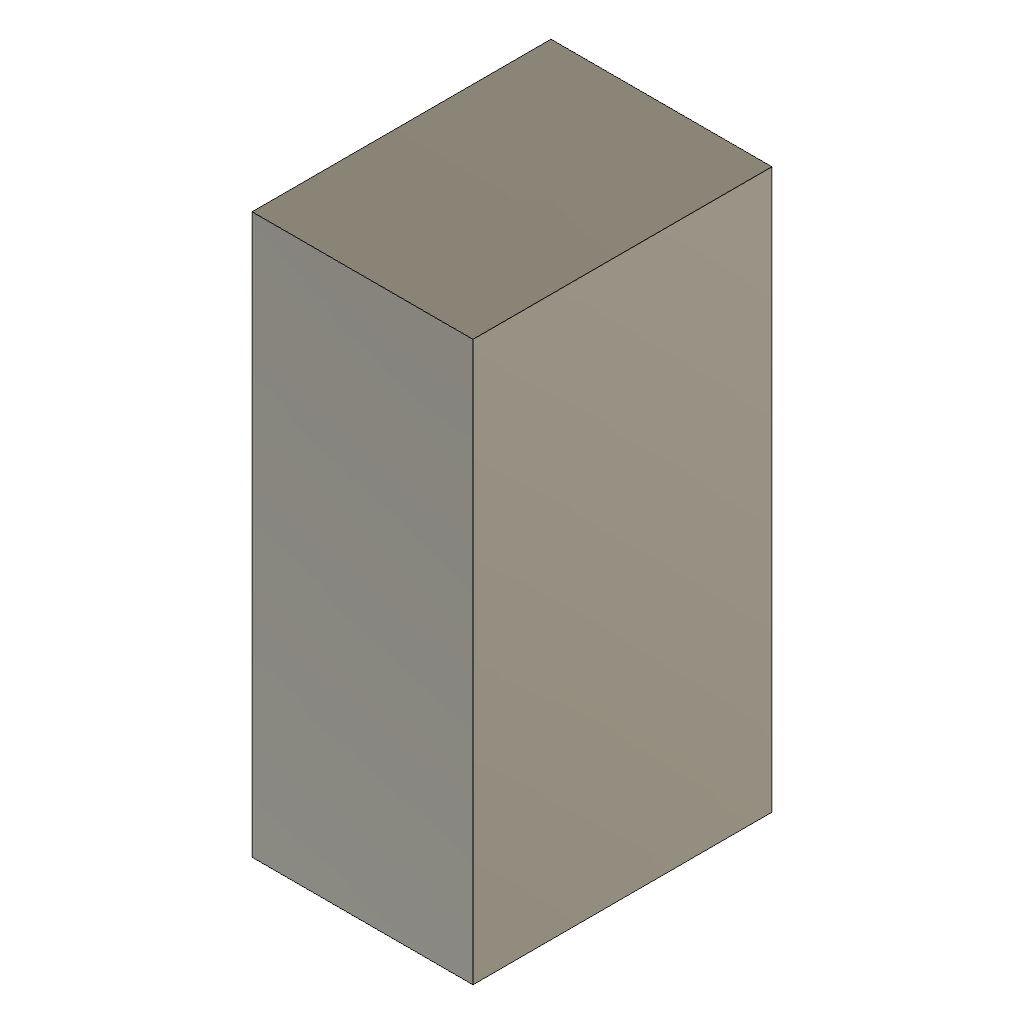
vendor_SavedCuboidReemittedEdited (Autodesk Fusion 360 design; units mm, degrees)
Autodesk Fusion 360 part; units mm, degrees
sketch "Authored Rectangle" plane through (0, 0, 0) normal (0, 0, 1) x (1, 0, 0)
  line L0 (0, 0) -> (17, 0)
  line L1 (17, 0) -> (17, 23)
  line L2 (17, 23) -> (0, 23)
  line L3 (0, 23) -> (0, 0)
extrude "Authored Cuboid Extrusion" add sketch "Authored Rectangle" along normal blind 43
equation "authoredLength = 43.0 mm" comment "Production native codec acceptance"
equation "d2 = authoredLength"
